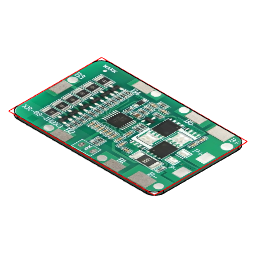
Loki v670 (Autodesk Fusion 360 archive; units mm, degrees)
design "XR-6S-JH2X3"
Autodesk Fusion 360 part; units mm, degrees
note: some values were not read from the file. Set by a fixed rule: which face or edge a step refers to.
sketch "Sketch1" plane through (0, 0, 0) normal (0, 0, 1) x (1, 0, 0)
  line L0 (25, -15.8) -> (-25, -15.8)
  line L1 (-25, -15.8) -> (-25, 15.8)
  line L2 (-25, 15.8) -> (25, 15.8)
  line L3 (25, 15.8) -> (25, -15.8)
  line L4 (0, 0) -> (-25, 0) construction
  line L5 (0, 0) -> (0, 15.8) construction
  dimension "d1" = 50
  dimension "d2" = 31.6
  constraint horizontal L0
  constraint perpendicular L0 L1
  constraint parallel L0 L2
  constraint parallel L1 L3
  constraint coincident L4.start L5.start
  constraint midpoint L1 L4.end
  constraint midpoint L2 L5.end
  constraint symmetric L0 L2 L4
  measures "d1" distance of L1.end L2.end
  measures "d2" distance of L0.start L2.end
extrude "Extrude1" add sketch "Sketch1" along normal blind 1
fillet "Fillet1" radius 3 4 edges at (-25, -15.8, 0.5) (25, -15.8, 0.5) (25, 15.8, 0.5) (-25, 15.8, 0.5)

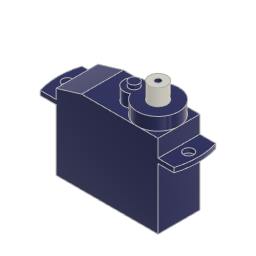
design "K-Power WK-P0025 servo"
Autodesk Fusion 360 part; units mm, degrees
sketch "Sketch1" plane through (0, 0, 0) normal (0, 0, 1) x (1, 0, 0)
  line L0 (10, -4.1) -> (-10, -4.1)
  line L1 (-10, -4.1) -> (-10, 4.1)
  line L2 (-10, 4.1) -> (10, 4.1)
  line L3 (10, 4.1) -> (10, -4.1)
  line L4 (10, -4.1) -> (-10, 4.1) construction
  line L5 (-10, -4.1) -> (10, 4.1) construction
  dimension "d1" = 20
  dimension "d2" = 8.2
  constraint horizontal L0
  constraint perpendicular L0 L1
  constraint parallel L0 L2
  constraint parallel L1 L3
  constraint coincident L4 origin
  constraint coincident L5 origin
  measures "d1" distance of L1.end L2.end
  measures "d2" distance of L0.end L1.end
extrude "Extrude1" add sketch "Sketch1" against normal blind 12
sketch "Sketch2" plane through (0, 0, 0) normal (0, 0, 1) x (-1, 0, 0)
  line L0 (-10, -4.1) -> (10, -4.1)
  line L1 (10, -4.1) -> (10, 4.1)
  line L2 (10, 4.1) -> (-10, 4.1)
  line L3 (-10, 4.1) -> (-10, -4.1)
  line L4 (0, 0) -> (-11.9, 0) construction
  line L5 (0, 0) -> (11.9, 0) construction
  circle A0 centre (-11.9, 0) radius 1
  circle A1 centre (11.9, 0) radius 1
  circle A2 centre (0, 0) radius 13.75
  line L6 (-10, 4.1) -> (10, 4.1)
  line L7 (10, -4.1) -> (-10, -4.1)
  line L8 (-10, 4.1) -> (-13.1245, 4.1)
  line L9 (-10, -4.1) -> (-13.1245, -4.1)
  line L10 (10, -4.1) -> (13.1245, -4.1)
  line L11 (10, 4.1) -> (13.1245, 4.1)
  dimension "d7" = 23.8
  dimension "d8" = 2
  dimension "d10" = 27.5
  constraint coincident L4.start L5.start
  constraint perpendicular L3 L4
  constraint perpendicular L3 L5
  constraint equal L4 L5
  constraint coincident L4.end A0.centre
  constraint coincident L5.end A1.centre
  constraint equal A0 A1
  constraint coincident L2.end L3.start
  constraint coincident A2 L8.end
  constraint perpendicular L3 L8
  constraint coincident L0.start L3.end
  constraint coincident A2 L9.end
  constraint perpendicular L3 L9
  constraint coincident L0.end L1.start
  constraint coincident A2 L10.end
  constraint perpendicular L1 L10
  constraint coincident L1.end L2.start
  constraint coincident A2 L11.end
  constraint perpendicular L1 L11
  measures "d7" distance of L4.end L5.end
  measures "d8" diameter of A0
  measures "d10" diameter of A2
extrude "Extrude2" add 1 faces at (-3.3333, -1.3667, 0) along direction (0, 0, 1) blind 4.3
extrude "Extrude3" add sketch "Sketch2" along normal blind 0.9 contours L3 A2 L8 L9 | L1 A2 L10 L11
sketch "Sketch3" plane through (0, -4.1, 0) normal (0, -1, 0) x (1, 0, 0)
  line L0 (-10, 0) -> (-10, -12)
  line L1 (-10, -12) -> (10, -12)
  line L2 (10, -12) -> (10, 0)
  line L3 (10, 4.3) -> (-10, 4.3)
  line L4 (-10, 2.8) -> (-5, 4.3)
  line L5 (10, 0) -> (13.1245, 0)
  line L6 (13.1245, 0) -> (13.1245, 0.9)
  line L7 (13.1245, 0.9) -> (10, 0.9)
  line L8 (10, 0.9) -> (10, 4.3)
  line L9 (-10, 4.3) -> (-10, 0.9)
  line L10 (-10, 0.9) -> (-13.1245, 0.9)
  line L11 (-13.1245, 0.9) -> (-13.1245, 0)
  line L12 (-13.1245, 0) -> (-10, 0)
  dimension "d13" = 1.5
  dimension "d14" = 5
  constraint coincident L0 L4.start
  constraint coincident L3 L4.end
  measures "d13" distance of L3 L4.start
  measures "d14" distance of L0 L4.end
extrude "Extrude4" cut sketch "Sketch3" against normal through all contours L3 L4 L9
sketch "Sketch4" plane through (0, 0, 4.3) normal (0, 0, 1) x (-1, 0, 0)
  line L0 (5, -4.1) -> (5, 4.1)
  line L1 (5, 4.1) -> (-10, 4.1)
  line L2 (-10, 4.1) -> (-10, -4.1)
  line L3 (-10, -4.1) -> (5, -4.1)
  line L4 (-5.9, 0) -> (-10, 0) construction
  circle A0 centre (-5.9, 0) radius 4.1
  line L5 (-5.9, 0) -> (-5.9, -4.1)
  line L6 (-5.9, 0) -> (-1.2, 0) construction
  circle A1 centre (-1.2, 0) radius 2
  line L7 (-1.2, 0) -> (0.8, 0) construction
  dimension "d16" = 4
  dimension "d17" = 10.8
  constraint midpoint L2 L4.end
  constraint perpendicular L2 L4
  constraint coincident L4.start A0.centre
  constraint tangent L3 A0
  constraint coincident A0 L5.end
  constraint perpendicular L3 L5
  constraint coincident L4.end A0
  constraint perpendicular L5 L6
  constraint coincident L6.end A1.centre
  constraint coincident A1 L7.end
  constraint parallel L6 L7
  measures "d16" diameter of A1
  measures "d17" distance of L4.end L7.end
extrude "Extrude5" add sketch "Sketch4" along normal blind 2.5 contours A0 A1 | A0 A1 | A0 A1
sketch "Sketch5" plane through (0, 0, 6.8) normal (0, 0, 1) x (-1, 0, 0)
  arc A0 (-2.1872, -1.7394) -> (-2.1872, 1.7394) centre (-1.2, 0) ccw
  arc A1 (-2.1872, 1.7394) -> (-2.1872, -1.7394) centre (-5.9, 0) ccw
  circle A2 centre (-5.9, 0) radius 1.75
  circle A3 centre (-1.2, 0) radius 1
  dimension "d20" = 3.5
  dimension "d23" = 2
  constraint concentric A1 A2
  constraint concentric A0 A3
  measures "d20" diameter of A2
  measures "d23" diameter of A3
extrude "Extrude6" add sketch "Sketch5" along normal blind 3.2 contours A2
extrude "Extrude7" add sketch "Sketch5" along normal blind 0.8 contours A3
sketch "Sketch6" plane through (0, 0, 10) normal (0, 0, 1) x (-1, 0, 0)
  circle A0 centre (-5.9, 0) radius 1.75
  circle A1 centre (-5.9, 0) radius 0.6
  dimension "d43" = 1.2
  constraint concentric A0 A1
  measures "d43" diameter of A1
extrude "Extrude8" cut sketch "Sketch6" against normal up to surface (3.2 mm away) contours A1
equation "angle = 90 deg"

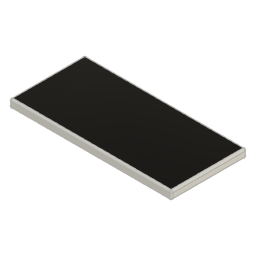
design "Smartphone"
Autodesk Fusion 360 part; units mm, degrees
sketch "Body" plane through (0, 0, 0) normal (0, 0, 1) x (1, 0, 0)
  line L0 (-83.45, 39.05) -> (83.45, 39.05)
  line L1 (83.45, 39.05) -> (83.45, -39.05)
  line L2 (83.45, -39.05) -> (-83.45, -39.05)
  line L3 (-83.45, -39.05) -> (-83.45, 39.05)
  line L4 (0, 39.05) -> (0, 0) construction
  line L5 (-83.45, 0) -> (0, 0)
  dimension "d7" = 78.1
  dimension "d11" = 166.9
  constraint horizontal L0
  constraint vertical L1
  constraint horizontal L2
  constraint vertical L3
  constraint midpoint L0 L4.start
  constraint coincident L4.end L5.end
  constraint midpoint L3 L5.start
  constraint horizontal L5
  constraint vertical L4
  measures "d7" distance of L0.end L1.end
  measures "d11" distance of L0.start L0.end
extrude "Extrude1" add sketch "Body" along normal blind 9
sketch "Corners" plane through (0, 0, 0) normal (0, 0, -1) x (1, 0, 0)
  line L0 (83.45, 39.05) -> (-83.45, 39.05)
  line L1 (-83.45, 39.05) -> (-83.45, -39.05)
  line L2 (-83.45, -39.05) -> (83.45, -39.05)
  line L3 (83.45, -39.05) -> (83.45, 39.05)
  line L4 (83.45, 39.05) -> (-83.45, 39.05)
  line L5 (-83.45, -39.05) -> (83.45, -39.05)
  line L6 (0, 39.05) -> (0, -39.05) construction
  constraint midpoint L4 L6.start
  constraint midpoint L5 L6.end
fillet "Fillet1" radius 2 7 faces at (27.8167, 0, 9) (27.8167, 0, 0) (27.8167, -39.05, 3) (83.45, 13.0167, 6) (-27.8167, 39.05, 3) (-83.45, -26.0333, 6) (-83.45, 13.0167, 6)
sketch "Joints" plane through (0, 0, 0) normal (1, 0, 0) x (0, 1, 0)
  circle A0 centre (-39.05, 0) radius 2.5
  circle A1 centre (39.05, 0) radius 2.5
  point P0 (-39.05, 0)
  point P1 (39.05, 0)
  dimension "d17" = 5
  dimension "d18" = 5
  constraint coincident P0 A0.centre
  constraint coincident P1 A1.centre
  measures "d17" diameter of A0
  measures "d18" diameter of A1
equation "maxPhoneHeight = 166.9 mm"
equation "minPhoneHeight = 131.5 mm"
equation "maxPhoneWidth = 78.1 mm"
equation "minPhoneWidth = 64.2 mm"
equation "maxPhoneDepth = 9 mm"
equation "minPhoneDepth = 7.3 mm"
equation "d7 = phoneWidth"
equation "phoneWidth = maxPhoneWidth"
equation "phoneHeight = maxPhoneHeight"
equation "phoneDepth = maxPhoneDepth"
equation "d11 = phoneHeight"
equation "d12 = phoneDepth"
equation "maxCaseThickness = 5 mm"

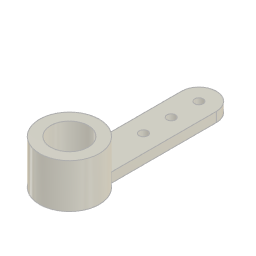
design "Servo single arm"
Autodesk Fusion 360 part; units mm, degrees
sketch "Sketch1" plane through (0, 0, 0) normal (0, 0, 1) x (1, 0, 0)
  line L0 (0, 0) -> (0, 6.9) construction
  circle A0 centre (0, 6.9) radius 0.4
  line L1 (0, 6.9) -> (0, 9.48) construction
  circle A1 centre (0, 9.48) radius 0.4
  line L2 (0, 9.48) -> (0, 12.06) construction
  circle A2 centre (0, 12.06) radius 0.4
  line L3 (0, 12.06) -> (-1.625, 12.06) construction
  line L4 (0, 12.06) -> (1.625, 12.06) construction
  line L5 (1.625, 12.06) -> (1.625, 2.2494)
  line L6 (-1.625, 12.06) -> (-1.625, 2.2494)
  arc A3 (1.625, 12.06) -> (-1.625, 12.06) centre (0, 12.06) ccw
  line L7 (0, 0) -> (0, -2.775) construction
  line L8 (0, 12.06) -> (0, 13.685) construction
  arc A4 (-1.625, 2.2494) -> (1.625, 2.2494) centre (0, 0) ccw
  circle A5 centre (0, 0) radius 0.8
  dimension "d1" = 5.55
  dimension "d2" = 0.8
  dimension "d3" = 2.58
  dimension "d4" = 3.25
  dimension "d5" = 16.46
  dimension "d6" = 1.6
  constraint coincident L0.start L7.start
  constraint vertical L0
  constraint coincident L0.end A0.centre
  constraint parallel L0 L1
  constraint coincident L1.end A1.centre
  constraint equal A0 A1
  constraint parallel L1 L2
  constraint coincident L2.end A2.centre
  constraint equal A0 A2
  constraint equal L1 L2
  constraint concentric A2 A3
  constraint perpendicular L2 L3
  constraint parallel L3 L4
  constraint tangent L5 A3
  constraint tangent L6 A3
  constraint coincident L7.end A4
  constraint vertical L7
  constraint midpoint A3 L8.end
  constraint concentric A4 A5
  measures "d1" diameter of A4
  measures "d2" diameter of A0
  measures "d3" distance of L1.end L2.end
  measures "d4" diameter of A3
  measures "d5" distance of L7.end L8.end
  measures "d6" diameter of A5
extrude "Extrude1" add sketch "Sketch1" along normal blind 0.9
sketch "Sketch2" plane through (0, 0, 0.9) normal (0, 0, 1) x (-1, 0, 0)
  circle A0 centre (0, 0) radius 0.8
  circle A1 centre (0, -6.9) radius 0.4
  circle A2 centre (0, -12.06) radius 0.4
  circle A3 centre (0, -9.48) radius 0.4
  arc A4 (-1.625, -12.06) -> (1.625, -12.06) centre (0, -12.06) ccw
  line L0 (1.625, -12.06) -> (1.625, -2.2494)
  arc A5 (1.625, -2.2494) -> (-1.625, -2.2494) centre (0, 0) ccw
  line L1 (-1.625, -2.2494) -> (-1.625, -12.06)
  circle A6 centre (0, 0) radius 1.75
  circle A7 centre (0, 0) radius 2.775
  dimension "d9" = 3.5
  constraint coincident A0.centre A5.centre
  constraint concentric A6 A7
  constraint coincident A5.end A7
  measures "d9" diameter of A6
extrude "Extrude2" add sketch "Sketch2" along normal blind 3.2 contours A5 A7

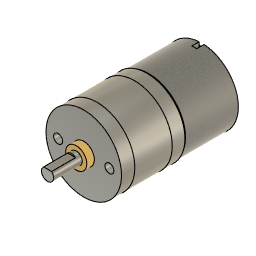
design "CHR-GM25-BL2418"
Autodesk Fusion 360 part; units mm, degrees
sketch "Sketch1" plane through (0, 0, 0) normal (0, 1, 0) x (1, 0, 0)
  circle A0 centre (0, 0) radius 12.5
  dimension "d1" = 25
  constraint coincident A0.centre origin
  measures "d1" diameter of A0
extrude "Extrude1" add sketch "Sketch1" along normal blind 4.4 makes body 1
extrude "Extrude4" add 1 faces at (-3.3879, 4.4, 0.621) along direction (0, 1, 0) blind 12.4 separate body on bodies 1 makes body 2
extrude "Extrude5" add 1 faces at (-3.3879, 16.8, 0.621) along direction (0, 1, 0) blind 4.2 separate body on bodies 2 makes body 3
sketch "Sketch2" plane through (0, 21, 0) normal (0, 1, 0) x (-1, 0, 0)
  circle A0 centre (0, 0) radius 12.5
  circle A1 centre (0, 0) radius 12.2
  circle A2 centre (0, 0) radius 12.5
  dimension "d6" = 24.4
  constraint coincident A0.centre A1.centre
  measures "d6" diameter of A1
extrude "Extrude3" add sketch "Sketch2" along normal blind 18 separate body contours A1 makes body 4
fillet "Fillet1" radius 0.5 1 edges at (11.3744, 21, -4.4117) on bodies 4
sketch "Sketch3" plane through (0, 0, 0) normal (0, -1, 0) x (1, 0, 0)
  circle A0 centre (0, 0) radius 12.5
  circle A1 centre (0, 0) radius 3.5
  circle A2 centre (0, 0) radius 2
  dimension "d15" = 7
  dimension "d18" = 4
  constraint coincident A0.centre A1.centre
  constraint concentric A1 A2
  measures "d15" diameter of A1
  measures "d18" diameter of A2
extrude "Extrude6" add sketch "Sketch3" along normal blind 2.5 separate body contours A1 makes body 5
extrude "Extrude7" add sketch "Sketch3" along normal blind 12 separate body contours A2 makes body 6
sketch "Sketch4" plane through (0, -12, 0) normal (0, -1, 0) x (1, 0, 0)
  circle A0 centre (0, 0) radius 2
  circle A1 centre (0, 0) radius 2
  line L0 (-1.3229, 1.5) -> (1.3229, 1.5)
  dimension "d22" = 1.5
  constraint horizontal L0
  constraint coincident A1 L0.end
  constraint coincident A1 L0.start
  measures "d22" distance of L0 A0.centre
extrude "Extrude8" cut sketch "Sketch4" against normal blind 8 contours A0 A1 L0 picked at (-0.3643, 1.5583) bodies 1 6
sketch "Sketch5" plane through (0, 39, 0) normal (0, 1, 0) x (-1, 0, 0)
  circle A0 centre (0, 0) radius 12.2
  line L0 (-3.5, 10.2) -> (3.5, 10.2)
  line L1 (3.5, 10.2) -> (3.5, 7.2)
  line L2 (3.5, 7.2) -> (-3.5, 7.2)
  line L3 (-3.5, 7.2) -> (-3.5, 10.2)
  line L4 (0, 7.2) -> (0, 0)
  line L5 (0, 10.2) -> (0, 12.2) construction
  dimension "d25" = 7
  dimension "d26" = 3
  dimension "d27" = 5
  constraint horizontal L0
  constraint vertical L1
  constraint horizontal L2
  constraint vertical L3
  constraint midpoint L2 L4.start
  constraint coincident A0.centre L4.end
  constraint vertical L4
  constraint midpoint L0 L5.start
  constraint coincident A0 L5.end
  constraint perpendicular L0 L5
  measures "d25" distance of L0.start L0.end
  measures "d26" distance of L0.end L1.end
  measures "d27" distance of L4.start L5.end
extrude "Extrude9" add sketch "Sketch5" along normal blind 1 separate body contours L0 L1 L2 L3 makes body 7
sketch "Sketch6" plane through (0, 0, 0) normal (0, -1, 0) x (1, 0, 0)
  circle A0 centre (0, 0) radius 12.5
  line L0 (0, 0) -> (8.5, 0) construction
  line L1 (0, 0) -> (-8.5, 0) construction
  circle A1 centre (8.5, 0) radius 1.5
  circle A2 centre (-8.5, 0) radius 1.5
  dimension "d30" = 3
  dimension "d31" = 17
  constraint coincident A0.centre L0.start
  constraint horizontal L0
  constraint parallel L0 L1
  constraint equal L0 L1
  constraint coincident L0.end A1.centre
  constraint coincident L1.end A2.centre
  constraint equal A1 A2
  measures "d30" diameter of A1
  measures "d31" distance of L0.end L1.end
extrude "Extrude10" cut sketch "Sketch6" against normal through all contours A1 | A2 bodies 1 6
sketch "Sketch7" plane through (0, 39, 0) normal (0, 1, 0) x (-1, 0, 0)
  circle A0 centre (0, 0) radius 12.2
  circle A1 centre (0, 0) radius 3.2
  dimension "d34" = 6.4
  constraint coincident A0.centre A1.centre
  measures "d34" diameter of A1
extrude "Extrude11" add sketch "Sketch7" along normal blind 1.3 contours A1 bodies 4
sketch "Sketch8" plane through (0, 40.3, 0) normal (0, 1, 0) x (-1, 0, 0)
  circle A0 centre (0, 0) radius 3.2
  circle A1 centre (0, 0) radius 1
  dimension "d37" = 2
  constraint coincident A0.centre A1.centre
  measures "d37" diameter of A1
extrude "Extrude12" add sketch "Sketch8" along normal blind 1 separate body contours A1 makes body 8
sketch "Sketch9" plane through (0, 40, 0) normal (0, 1, 0) x (-1, 0, 0)
  line L0 (-3.5, 7.2) -> (3.5, 7.2)
  line L1 (3.5, 7.2) -> (3.5, 10.2)
  line L2 (3.5, 10.2) -> (-3.5, 10.2)
  line L3 (-3.5, 10.2) -> (-3.5, 7.2)
  line L4 (3.1, 9.8) -> (-3.1, 9.8)
  line L5 (-3.1, 9.8) -> (-3.1, 7.6)
  line L6 (-3.1, 7.6) -> (3.1, 7.6)
  line L7 (3.1, 7.6) -> (3.1, 9.8)
  dimension "d40" = -0.4
extrude "Extrude13" cut sketch "Sketch9" against normal blind 0.8 contours L4 L5 L6 L7 bodies 7
ref_plane "WorkPlane2" through (0, 31.2239, 12.2) normal (0, 0, 1) x (-1, 0, 0)
sketch "Sketch10" plane through (0, 31.2239, 12.2) normal (0, 0, 1) x (1, 0, 0)
  line L0 (12.2, 7.7761) -> (-12.2, 7.7761)
  line L1 (0, 0) -> (0, 7.7761) construction
  line L2 (0, 5.3761) -> (0.8, 5.3761)
  line L3 (0.8, 5.3761) -> (0.8, 7.7761)
  line L4 (0, 5.3761) -> (-0.8, 5.3761)
  line L5 (-0.8, 5.3761) -> (-0.8, 7.7761)
  dimension "d44" = 1.6
  dimension "d45" = 2.4
  constraint coincident L1.start origin
  constraint midpoint L0 L1.end
  constraint coincident L1 L2.start
  constraint perpendicular L1 L2
  constraint coincident L0 L3.end
  constraint perpendicular L0 L3
  constraint perpendicular L1 L4
  constraint coincident L0 L5.end
  constraint perpendicular L0 L5
  constraint equal L2 L4
  measures "d44" distance of L2.end L4.end
  measures "d45" distance of L2.end L3.end
extrude "Extrude14" cut sketch "Sketch10" against normal up to surface (2 mm away) bodies 4
equation "d11 = 21 mm - 4.4 mm - 4.2 mm"
named bodies: "Gearbox", "Motor"
